Autodesk Fusion 360 part; units mm, degrees
(part 3 of 3)
component "left forward carriage sleeve" placed x (1, 0, 0) y (0, 1, 0) z (0, 0, 1) at (-180, 326, 682)
component "left aft carriage sleeve" placed x (1, 0, 0) y (0, 1, 0) z (0, 0, 1) at (-280, 326, 682)
component "left extension sleeve" placed x (0, 1, 0) y (0, 0, 1) z (1, 0, 0) at (-173, 72, 739)
component "left sleeve pedestal" placed x (1, 0, 0) y (0, 1, 0) z (0, 0, 1) at (-153, 72, 701)
component "left extending rail" placed x (0, 1, 0) y (0, 0, 1) z (1, 0, 0) at (-220, 72, 739)
component "left crown hook" placed x (1, 0, 0) y (0, 0, 1) z (0, -1, 0) at (0, 94, 0)
component "right mast" placed x (1, 0, 0) y (0, 1, 0) z (0, 0, 1) at (-180, -326, 114.8)
component "right aft mast" placed x (1, 0, 0) y (0, 1, 0) z (0, 0, 1) at (-280, -326, 114.8)
component "right upper bearing plate" placed x (1, 0, 0) y (0, 1, 0) z (0, 0, 1) at (-230, -317, 744)
component "right lower bearing plate" placed x (1, 0, 0) y (0, 1, 0) z (0, 0, 1) at (-240, -313.5, 551)
component "right lead screw envelope" placed x (1, 0, 0) y (0, 1, 0) z (0, 0, 1) at (-240, -305, 557)
component "right lift motor envelope" placed x (1, 0, 0) y (0, 1, 0) z (0, 0, 1) at (-240, -258, 577)
component "right reduction envelope" placed x (1, 0, 0) y (0, 1, 0) z (0, 0, 1) at (-240, -280, 557)
component "right driven nut" placed x (1, 0, 0) y (0, 1, 0) z (0, 0, 1) at (-240, -305.5, 711)
component "right nut link" placed x (1, 0, 0) y (0, 1, 0) z (0, 0, 1) at (-240, -306, 701)
component "right crosshead cheek" placed x (1, 0, 0) y (0, 1, 0) z (0, 0, 1) at (-204.5, -303.5, 687)
component "right forward carriage sleeve" placed x (1, 0, 0) y (0, 1, 0) z (0, 0, 1) at (-180, -326, 682)
component "right aft carriage sleeve" placed x (1, 0, 0) y (0, 1, 0) z (0, 0, 1) at (-280, -326, 682)
component "right extension sleeve" placed x (0, 1, 0) y (0, 0, 1) z (1, 0, 0) at (-173, -72, 739)
component "right sleeve pedestal" placed x (1, 0, 0) y (0, 1, 0) z (0, 0, 1) at (-153, -72, 701)
component "right extending rail" placed x (0, 1, 0) y (0, 0, 1) z (1, 0, 0) at (-220, -72, 739)
component "right crown hook" placed x (1, 0, 0) y (0, 0, 1) z (0, -1, 0) at (0, -82, 0)
component "crosshead lift bridge" placed x (-1, 0, 0) y (0, 0, 1) z (0, 1, 0) at (-151, -315, 691)
component "rail synchronizing tie" placed x (1, 0, 0) y (0, 1, 0) z (0, 0, 1) at (163, 0, 750)
component "extension bearing beam" placed x (1, 0, 0) y (0, 1, 0) z (0, 0, 1) at (32, 0, 701)
component "extension rear bearing and stop" placed x (0, 1, 0) y (0, 0, 1) z (1, 0, 0) at (-74, 0, 733)
component "extension forward bearing" placed x (0, 1, 0) y (0, 0, 1) z (1, 0, 0) at (193, 0, 733)
component "extension screw envelope" placed x (0, 1, 0) y (0, 0, 1) z (1, 0, 0) at (-74, 0, 733)
component "extension deployment nut" placed x (0, 1, 0) y (0, 0, 1) z (1, 0, 0) at (153, 0, 733)
component "extension nut hanger" placed x (1, 0, 0) y (0, 1, 0) z (0, 0, 1) at (163, 0, 746)
component "extension motor envelope" placed x (0, 1, 0) y (0, 0, 1) z (1, 0, 0) at (205, 0, 733)
component "extension motor foot" placed x (1, 0, 0) y (0, 1, 0) z (0, 0, 1) at (215, 0, 716)
component "right blue side bumper" placed x (1, 0, 0) y (0, 1, 0) z (0, 0, 1) at (0, -378, 48) in component "rail synchronizing tie"
named bodies: "left perimeter tube", "left front return", "left blue side bumper", "left blue front bumper", "right perimeter tube", "right front return", "right blue side bumper", "right blue front bumper", "rear perimeter tube", "rear blue bumper", "front left module tab spacer 1", "front left module tab spacer 2", "front right module tab spacer 1", "front right module tab spacer 2", "rear left module tab spacer 1", "rear left module tab spacer 2", "rear right module tab spacer 1", "rear right module tab spacer 2", "rear right hopper post", "front right hopper post", "right floor sill", "rear left hopper post", "front left hopper post", "left floor sill", "rear deck crossmember", "front deck crossmember", "left electronics deck", "right electronics deck", "fore electronics deck bridge", "aft electronics deck bridge", "battery cradle floor", "battery cradle wall -44", "battery cradle wall 43", "battery secured envelope", "distribution enclosure reserve", "robot controller reserve", "field radio reserve", "drive controller reserve 1", "drive controller reserve 2", "drive controller reserve 3", "drive controller reserve 4", "drive controller reserve 5", "drive controller reserve 6", "drive controller reserve 7", "drive controller reserve 8", "hopper back panel", "right hopper wall", "right hopper front wing", "right cross feed deck", "right front elevator upright", "right rear elevator upright", "right elevator upper tie", "right inside lift belt", "right outside lift belt", "right lift shelf 1", "right lift shelf 2", "right lift shelf 3", "right lift shelf 4", "right intake ramp", "left hopper wall", "left hopper front wing", "left cross feed deck", "left front elevator upright", "left rear elevator upright", "left elevator upper tie", "left inside lift belt", "left outside lift belt", "left lift shelf 1", "left lift shelf 2", "left lift shelf 3", "left lift shelf 4", "left intake ramp", "central fore-aft feed deck", "left lower lift stub shaft", "right lower lift stub shaft", "left upper lift stub shaft", "right upper lift stub shaft", "ground intake roller", "right intake bearing arm", "right intake pivot plate", "right intake pivot axle", "right intake journal", "right upper head cheek", "left intake bearing arm", "left intake pivot plate", "left intake pivot axle", "left intake journal", "left upper head cheek", "right scoring wheel", "right scoring spindle", "right upper guide", "right scoring bearing bridge -33", "right scoring bearing bridge 33", "left scoring wheel", "left scoring spindle", "left upper guide", "left scoring bearing bridge -33", "left scoring bearing bridge 33", "left feed diverter pivot", "right feed diverter pivot", "feed diverter vane", "front left public wheel", "front left public drive housing", "front left public motor reserve", "front right public wheel", "front right public drive housing", "front right public motor reserve", "rear left public wheel", "rear left public drive housing", "rear left public motor reserve", "rear right public wheel", "rear right public drive housing", "rear right public motor reserve", "right public scoring motor envelope", "left public scoring motor envelope", "rear lift custody gate", "front lift custody guide", "left mast", "left aft mast", "left upper bearing plate", "left lower bearing plate", "left lead screw envelope", "left lift motor envelope", "left reduction envelope", "left driven nut", "left nut link", "left crosshead cheek", "left forward carriage sleeve", "left aft carriage sleeve", "left extension sleeve", "left sleeve pedestal", "left extending rail", "left crown hook", "right mast", "right aft mast", "right upper bearing plate", "right lower bearing plate", "right lead screw envelope", "right lift motor envelope", "right reduction envelope", "right driven nut", "right nut link", "right crosshead cheek", "right forward carriage sleeve", "right aft carriage sleeve", "right extension sleeve", "right sleeve pedestal", "right extending rail", "right crown hook", "crosshead lift bridge", "rail synchronizing tie", "extension bearing beam", "extension rear bearing and stop", "extension forward bearing", "extension screw envelope", "extension deployment nut", "extension nut hanger", "extension motor envelope", "extension motor foot"
